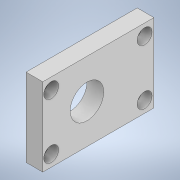
# Autodesk Inventor part: Subconjunto palanca - pieza eje
Saved by Autodesk Inventor 2020.2 (Build 242310000, 310)
## iProperties
Created: 2020-09-28
Part Number: Subconjunto palanca - pieza eje
Material: Genérico
Document SubType Name: Modeling
Designer: Salvador
Density: 1 g/cm^3
Appearance: Valor por defecto
Author: Salvador
Autodesk Inventor part; units mm, degrees
ref_plane "YZ Plane" through (0, 0, 0) normal (1, 0, 0) x (0, 1, 0)
ref_plane "XZ Plane" through (0, 0, 0) normal (0, 1, 0) x (-1, 0, 0)
ref_plane "XY Plane" through (0, 0, 0) normal (0, 0, 1) x (1, 0, 0)
sketch "Boceto1" plane through (0, 0, 0) normal (1, 0, 0) x (0, 1, 0)
  line L0 (0, -69.65) -> (0, 69.65) projected
  line L1 (-49, 0) -> (49, 0) projected
  line L2 (35, 49.75) -> (-35, 49.75)
  line L3 (-35, 49.75) -> (-35, -49.75)
  line L4 (-35, -49.75) -> (35, -49.75)
  line L5 (35, -49.75) -> (35, 49.75)
  line L6 (35, 49.75) -> (-35, -49.75) construction
  line L7 (-35, 49.75) -> (35, -49.75) construction
  circle A0 centre (24.75, 42.25) radius 4
  circle A1 centre (0, 10.23) radius 15.015
  circle A2 centre (-24.75, 42.25) radius 4
  circle A3 centre (24.75, -41.35) radius 4
  circle A4 centre (-24.75, -41.35) radius 4
  point P0 (0, 0)
  dimension "d0" = 70
  dimension "d1" = 99.5
  dimension "d2" = 8
  dimension "d3" = 24.75
  dimension "d4" = 7.5
  dimension "d5" = 30.03
  dimension "d6" = 0
  dimension "d7" = 10.23
  dimension "d56" = 24.75
  dimension "d57" = 8
  dimension "d58" = 10.25
  dimension "d59" = 8.4
  dimension "d60" = 10.25
  constraints: 12 end point, 5 centre point, 2 midpoint, 2 parallel, 2 symmetric about line, 1 horizontal, 1 perpendicular, 2 other
  measures "d0" distance of L4.end L3.end
  measures "d1" distance of L3.end L2.end
  measures "d2" diameter of A0
  measures "d3" distance from line of L0 A0.centre
  measures "d4" distance from line of L2 A0.centre
  measures "d5" diameter of A1
  measures "d6" distance from line of L0 A1.centre
  measures "d7" distance from line of L1 A1.centre
  measures "d56" distance from line of L0 A2.centre
  measures "d57" diameter of A3
  measures "d58" distance from line of L5 A3.centre
  measures "d59" distance from line of L4 A3.centre
  measures "d60" distance from line of L3 A4.centre
extrude "Extrusión1" add sketch "Boceto1" against normal blind 15 contours L4 L3 L1 A1 L0 | L0 A1 L1 L5 L4 | A1 L1 L0 | L0 L1 A1 | L1 A1 L0 | L0 A1 L1 | L1 L3 L2 L0 A1 | A1 L0 L2 L5 L1 | A0 | A2 | A3 | A4
hole "Agujero2" at (0, 0, 10.23) direction (-1, 0, 0) diameter 30.03 end through all
hole "Agujero7" at (0, -24.75, 42.25) direction (-1, 0, 0) diameter 8 depth 15 counterbore diameter 13.35 counterbore depth 9.03
hole "Agujero8" at (0, 24.75, 42.25) direction (-1, 0, 0) diameter 8 depth 15 counterbore diameter 13.35 counterbore depth 9.03
hole "Agujero9" at (0, 24.75, -41.35) direction (-1, 0, 0) diameter 8 depth 15 counterbore diameter 13.35 counterbore depth 9.03
hole "Agujero10" at (0, -24.75, -41.35) direction (-1, 0, 0) diameter 8 depth 15 counterbore diameter 13.35 counterbore depth 9.03
sketch "Boceto6" plane through (-9.03, 24.75, 42.25) normal (1, 0, 0) x (0, 0, -1)
  circle A0 centre (0, 0) radius 4 projected
  point P0 (42.25, -24.75)
  constraints: 1 coincident
hole "Agujero11" at (-9.03, 24.75, 42.25) direction (-1, 0, 0) diameter 8 depth 15 countersink diameter 13.35 countersink angle 90
sketch "Boceto7" plane through (-9.03, -24.75, 42.25) normal (1, 0, 0) x (0, 0, -1)
  circle A0 centre (0, 0) radius 4 projected
  point P0 (42.25, 24.75)
  constraints: 1 coincident
hole "Agujero12" at (-9.03, -24.75, 42.25) direction (-1, 0, 0) diameter 8 depth 15 countersink diameter 13.35 countersink angle 90
sketch "Boceto8" plane through (-9.03, 24.75, -41.35) normal (1, 0, 0) x (0, 0, -1)
  circle A0 centre (0, 0) radius 4 projected
  point P0 (-41.35, -24.75)
  constraints: 1 coincident
hole "Agujero13" at (-9.03, 24.75, -41.35) direction (-1, 0, 0) diameter 8 depth 15 countersink diameter 13.35 countersink angle 90
sketch "Boceto9" plane through (-9.03, -24.75, -41.35) normal (1, 0, 0) x (0, 0, -1)
  circle A0 centre (0, 0) radius 4 projected
  point P0 (-41.35, 24.75)
  constraints: 1 coincident
hole "Agujero14" at (-9.03, -24.75, -41.35) direction (-1, 0, 0) diameter 8 depth 15 countersink diameter 13.35 countersink angle 90
